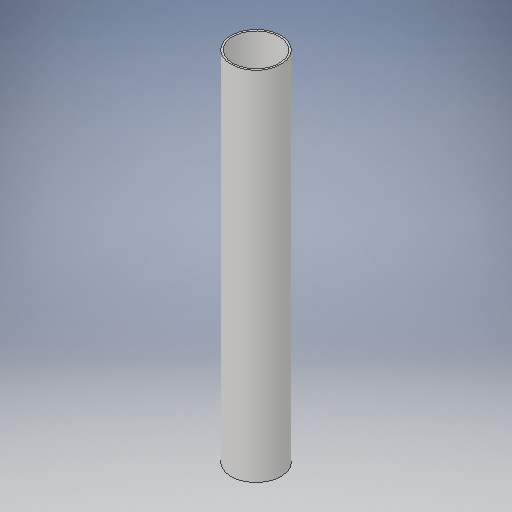
# Autodesk Inventor part: BT012_thutrn22_26
Saved by Autodesk Inventor 2025.3 (Build 293356000, 356)
## iProperties
Company: HTBLA Kaindorf
RuleStatus: InUse
Created: 2026-08-11
Part Number: BT012_thutrn22_26
Project: Biegeroboter
Material: Generisch
Description: Rohr
Document SubType Name: Modeling
Designer: thutrn22
Density: 1 g/cm^3
Appearance: Vorgabe
Mass: 2.12058 g
Surface Area: 85.2471 cm^2
Volume: 2.12058 cm^3
AfterDocNew0: iProperties-Editor_aufrufen
Author: trist
Keywords: 2026
Autodesk Inventor part; units mm, degrees
ref_plane "YZ Plane" through (0, 0, 0) normal (1, 0, 0) x (0, 1, 0)
ref_plane "XZ Plane" through (0, 0, 0) normal (0, 1, 0) x (-1, 0, 0)
ref_plane "XY Plane" through (0, 0, 0) normal (0, 0, 1) x (1, 0, 0)
sketch "Skizze3" plane through (0, 0, 0) normal (0, 0, 1) x (1, 0, 0)
  circle A0 centre (0, 0) radius 7
  circle A1 centre (0, 0) radius 6.5
  dimension "d4" = 14
  dimension "d5" = 13
  constraints: 2 centre point, 2 coincident
  measures "d4" diameter of A0
  measures "d5" diameter of A1
extrude "Extrusion3" add sketch "Skizze3" along normal blind 100
